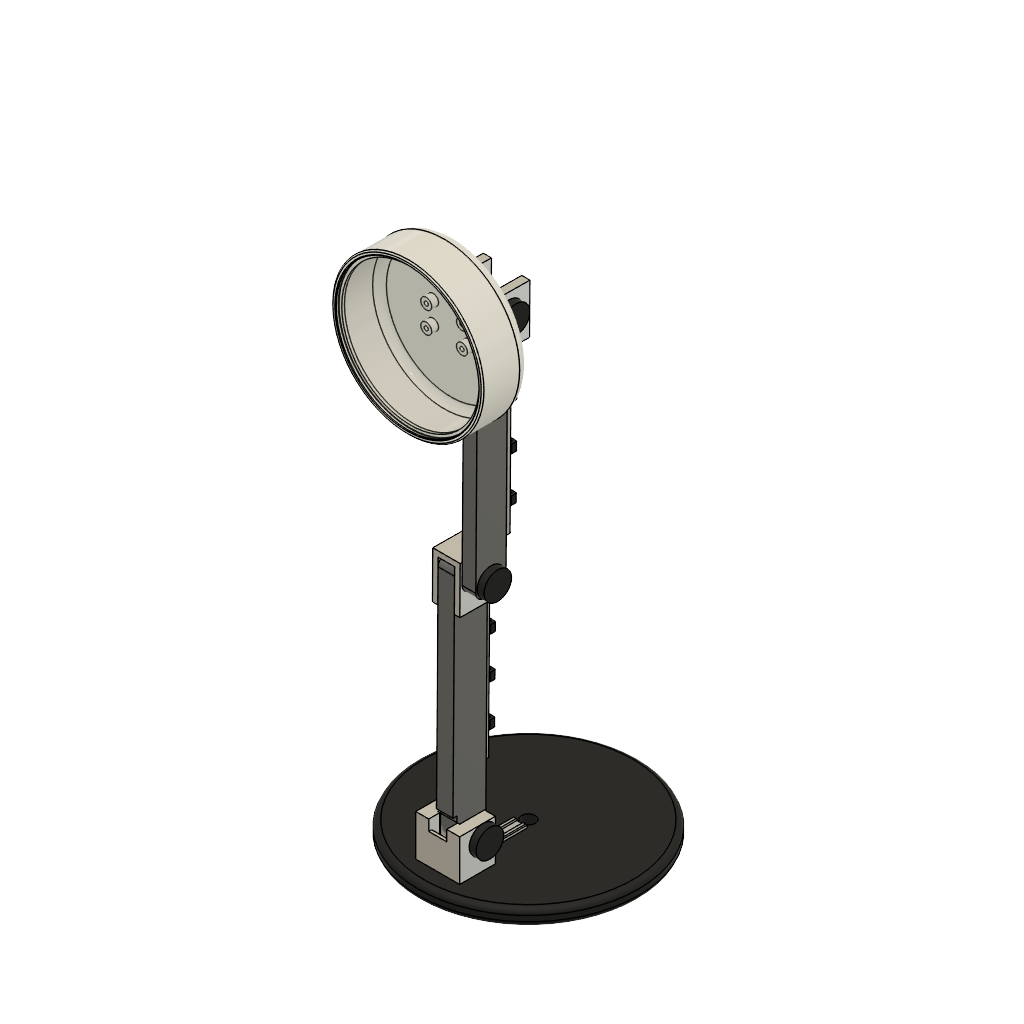
Desk_Lamp (Autodesk Fusion 360 design; units mm, degrees)
part number: 2026-11-22-08-35-22-088
part number: 2026-11-22-08-41-16-784
part number: 2026-11-22-08-41-16-816
part number: 2026-11-22-08-49-23-642
part number: 2026-11-22-08-49-23-668
part number: 2026-11-22-08-49-23-682
part number: 2026-11-22-09-13-58-178
part number: 2026-11-22-09-13-58-192
part number: 2026-11-22-09-13-58-206
part number: 2026-11-22-09-13-58-223
part number: 2026-11-22-09-22-23-851
part number: 2026-11-22-09-22-23-900
part number: 2026-11-22-09-22-23-921
part number: 2026-11-22-10-07-11-432
part number: 2026-11-22-10-07-39-371
part number: 2026-11-22-10-07-39-543
part number: 2026-11-22-10-22-32-254
part number: 2026-11-22-10-22-32-761
part number: 2026-11-22-10-22-33-482
part number: 2026-11-22-10-22-33-910
part number: 2026-11-22-10-22-34-385
part number: 2026-11-22-10-23-03-313
part number: 2026-11-22-10-23-03-986
part number: 2026-11-22-10-23-04-519
part number: 2026-11-22-10-23-04-941
Autodesk Fusion 360 part; units mm, degrees
sketch "Base Profile" plane through (0, 0, 0) normal (0, 0, 1) x (1, 0, 0) in component "Circular Base"
  circle A0 centre (0, 0) radius 80
extrude "Extrude1" add sketch "Base Profile" along normal blind 12 makes body 1 in component "Circular Base"
fillet "Fillet1" radius 4 2 edges at (-74.5862, -28.9292, 12) (-74.5862, -28.9292, 0) on bodies 1 in component "Circular Base"
sketch "Cable Hole" plane through (0, 0, 0) normal (0, 0, 1) x (1, 0, 0) in component "Circular Base"
  circle A0 centre (0, 0) radius 5
extrude "Extrude2" cut sketch "Cable Hole" along normal blind 12 bodies 1 in component "Circular Base"
sketch "Grip Recesses" plane through (0, 0, 0) normal (0, 0, 1) x (1, 0, 0) in component "Circular Base"
  circle A0 centre (42.4264, 42.4264) radius 7
  circle A1 centre (-42.4264, 42.4264) radius 7
  circle A2 centre (-42.4264, -42.4264) radius 7
  circle A3 centre (42.4264, -42.4264) radius 7
extrude "Extrude3" cut sketch "Grip Recesses" along normal blind 1.5 bodies 1 in component "Circular Base"
ref_plane "WorkPlane1" through (0, 0, 12) normal (0, 0, 1) x (1, 0, 0) in component "Base Support Bracket"
sketch "U Bracket Profile" plane through (0, 0, 12) normal (0, 0, 1) x (1, 0, 0) in component "Base Support Bracket"
  line L0 (-16, -66) -> (16, -66)
  line L1 (16, -66) -> (16, -40)
  line L2 (16, -40) -> (8, -40)
  line L3 (8, -40) -> (8, -58)
  line L4 (8, -58) -> (-8, -58)
  line L5 (-8, -58) -> (-8, -40)
  line L6 (-8, -40) -> (-16, -40)
  line L7 (-16, -40) -> (-16, -66)
extrude "Extrude1'" add sketch "U Bracket Profile" along normal blind 30 separate body makes body 2 in component "Base Support Bracket"
sketch "Pivot Holes" plane through (0, 0, 0) normal (1, 0, 0) x (0, 0, -1) in component "Base Support Bracket"
  circle A0 centre (-32, -49) radius 3
extrude "Extrude2'" cut sketch "Pivot Holes" along normal blind 20 and the other way blind 20 bodies 2 in component "Base Support Bracket"
sketch "Arm Profile" plane through (0, 0, 0) normal (1, 0, 0) x (0, 0, -1) in component "Lower Arm"
  line L0 (-30.1557, 18.8328) -> (149.8443, 18.8328)
  line L1 (149.8443, 18.8328) -> (149.8443, 42.8328)
  line L2 (149.8443, 42.8328) -> (-30.1557, 42.8328)
  line L3 (-30.1557, 42.8328) -> (-30.1557, 18.8328)
extrude "Extrude1''" add sketch "Arm Profile" along normal mid plane 12 separate body makes body 3 in component "Lower Arm"
fillet "Fillet1'" radius 6 4 edges at (0, 42.8328, 30.1557) (0, 42.8328, -149.8443) (0, 18.8328, -149.8443) (0, 18.8328, 30.1557) on bodies 3 in component "Lower Arm"
sketch "Arm Pivot Holes" plane through (0, 0, 0) normal (1, 0, 0) x (0, 0, -1) in component "Lower Arm"
  circle A0 centre (-22.1557, 30.8328) radius 3
  circle A1 centre (141.8443, 30.8328) radius 3
extrude "Extrude2''" cut sketch "Arm Pivot Holes" along normal mid plane 12 bodies 3 in component "Lower Arm"
sketch "Pin Profile" plane through (0, 0, 0) normal (1, 0, 0) x (0, 0, -1) in component "Base Pivot Pin"
  circle A0 centre (-22.1557, 30.8328) radius 3
extrude "Extrude1'''" add sketch "Pin Profile" along normal mid plane 32 separate body makes body 4 in component "Base Pivot Pin"
ref_plane "WorkPlane1" through (16, 0, 0) normal (1, 0, 0) x (0, 1, 0) in component "Adjustment Knob"
sketch "Knob Profile" plane through (16, 0, 0) normal (1, 0, 0) x (0, 0, -1) in component "Adjustment Knob"
  circle A0 centre (-22.1557, 30.8328) radius 10
extrude "Extrude1''''" add sketch "Knob Profile" along normal blind 5 separate body makes body 5 in component "Adjustment Knob"
ref_plane "WorkPlane1" through (15.5, 0, 0) normal (1, 0, 0) x (0, 1, 0) in component "Upper Arm"
sketch "Upper Arm Profile" plane through (15.5, 0, 0) normal (1, 0, 0) x (0, 0, -1) in component "Upper Arm"
  line L0 (133.8443, 19.8328) -> (293.8443, 19.8328)
  line L1 (293.8443, 19.8328) -> (293.8443, 41.8328)
  line L2 (293.8443, 41.8328) -> (133.8443, 41.8328)
  line L3 (133.8443, 41.8328) -> (133.8443, 19.8328)
extrude "Extrude1'''''" add sketch "Upper Arm Profile" along normal mid plane 10 separate body makes body 6 in component "Upper Arm"
fillet "Fillet1''" radius 6 4 edges at (15.5, 41.8328, -133.8443) (15.5, 41.8328, -293.8443) (15.5, 19.8328, -293.8443) (15.5, 19.8328, -133.8443) on bodies 6 in component "Upper Arm"
sketch "Upper Arm Pivot Holes" plane through (15.5, 0, 0) normal (1, 0, 0) x (0, 0, -1) in component "Upper Arm"
  circle A0 centre (141.8443, 30.8328) radius 3
  circle A1 centre (285.8443, 30.8328) radius 3
extrude "Extrude2'''" cut sketch "Upper Arm Pivot Holes" along normal mid plane 10 bodies 6 in component "Upper Arm"
ref_plane "WorkPlane1" through (0, 30.8328, 0) normal (0, 1, 0) x (0, 0, 1) in component "Elbow Joint Connector"
sketch "Clevis Profile" plane through (0, 30.8328, 0) normal (0, 1, 0) x (1, 0, 0) in component "Elbow Joint Connector"
  line L0 (-10, 153.8443) -> (10, 153.8443)
  line L1 (10, 153.8443) -> (10, 119.8443)
  line L2 (10, 119.8443) -> (6, 119.8443)
  line L3 (6, 119.8443) -> (6, 149.8443)
  line L4 (6, 149.8443) -> (-6, 149.8443)
  line L5 (-6, 149.8443) -> (-6, 119.8443)
  line L6 (-6, 119.8443) -> (-10, 119.8443)
  line L7 (-10, 119.8443) -> (-10, 153.8443)
extrude "Extrude1''''''" add sketch "Clevis Profile" along normal mid plane 24 separate body makes body 7 in component "Elbow Joint Connector"
sketch "Clevis Pivot Holes" plane through (0, 0, 0) normal (1, 0, 0) x (0, 0, -1) in component "Elbow Joint Connector"
  circle A0 centre (141.8443, 30.8328) radius 3
extrude "Extrude2''''" cut sketch "Clevis Pivot Holes" along normal mid plane 20 bodies 7 in component "Elbow Joint Connector"
ref_plane "WorkPlane1" through (5.25, 0, 0) normal (1, 0, 0) x (0, 1, 0) in component "Elbow Pivot Pin"
sketch "Elbow Pin Profile" plane through (5.25, 0, 0) normal (1, 0, 0) x (0, 0, -1) in component "Elbow Pivot Pin"
  circle A0 centre (141.8443, 30.8328) radius 3
extrude "Extrude1'''''''" add sketch "Elbow Pin Profile" along normal mid plane 30.5 separate body makes body 8 in component "Elbow Pivot Pin"
ref_plane "WorkPlane1" through (23, 0, 0) normal (1, 0, 0) x (0, 1, 0) in component "Elbow Adjustment Knob"
sketch "Elbow Knob Profile" plane through (23, 0, 0) normal (1, 0, 0) x (0, 0, -1) in component "Elbow Adjustment Knob"
  circle A0 centre (141.8443, 30.8328) radius 10
extrude "Extrude1''''''''" add sketch "Elbow Knob Profile" along normal mid plane 5 separate body makes body 9 in component "Elbow Adjustment Knob"
ref_plane "WorkPlane1" through (0, 30.8328, 0) normal (0, 1, 0) x (0, 0, 1) in component "Head Support Bracket"
sketch "Head Bracket Profile" plane through (0, 30.8328, 0) normal (0, 1, 0) x (1, 0, 0) in component "Head Support Bracket"
  line L0 (-1.5, 293.8443) -> (32.5, 293.8443)
  line L1 (32.5, 293.8443) -> (32.5, 329.8443)
  line L2 (32.5, 329.8443) -> (26.5, 329.8443)
  line L3 (26.5, 329.8443) -> (26.5, 299.8443)
  line L4 (26.5, 299.8443) -> (4.5, 299.8443)
  line L5 (4.5, 299.8443) -> (4.5, 329.8443)
  line L6 (4.5, 329.8443) -> (-1.5, 329.8443)
  line L7 (-1.5, 329.8443) -> (-1.5, 293.8443)
extrude "Extrude1'''''''''" add sketch "Head Bracket Profile" along normal mid plane 30 separate body makes body 10 in component "Head Support Bracket"
ref_plane "WorkPlane2" through (15.5, 0, 0) normal (1, 0, 0) x (0, 1, 0) in component "Head Support Bracket"
sketch "Head Pivot Holes" plane through (15.5, 0, 0) normal (1, 0, 0) x (0, 0, -1) in component "Head Support Bracket"
  circle A0 centre (314.8443, 30.8328) radius 3
extrude "Extrude2'''''" cut sketch "Head Pivot Holes" along normal mid plane 40 bodies 10 in component "Head Support Bracket"
ref_plane "WorkPlane1" through (15.5, 0, 0) normal (1, 0, 0) x (0, 1, 0) in component "Head Pivot Pin"
sketch "Head Pin Profile" plane through (15.5, 0, 0) normal (1, 0, 0) x (0, 0, -1) in component "Head Pivot Pin"
  circle A0 centre (314.8443, 30.8328) radius 3
extrude "Extrude1''''''''''" add sketch "Head Pin Profile" along normal mid plane 34 separate body makes body 11 in component "Head Pivot Pin"
ref_plane "WorkPlane1" through (35, 0, 0) normal (1, 0, 0) x (0, 1, 0) in component "Head Adjustment Knob"
sketch "Head Knob Profile" plane through (35, 0, 0) normal (1, 0, 0) x (0, 0, -1) in component "Head Adjustment Knob"
  circle A0 centre (314.8443, 30.8328) radius 10
extrude "Extrude1'''''''''''" add sketch "Head Knob Profile" along normal mid plane 5 separate body makes body 12 in component "Head Adjustment Knob"
ref_plane "WorkPlane1" through (0, 0, 42) normal (0, 0, 1) x (1, 0, 0) in component "Lamp Housing"
sketch "Housing Outer Profile" plane through (0, 0, 42) normal (0, 0, 1) x (1, 0, 0) in component "Lamp Housing"
  circle A0 centre (15.5, 367.82) radius 55
extrude "Extrude1''''''''''''" add sketch "Housing Outer Profile" along normal blind 35 separate body makes body 13 in component "Lamp Housing"
fillet "Fillet1'''" radius 8 1 edges at (-35.778, 347.9312, 42) on bodies 13 in component "Lamp Housing"
shell "Shell1" thickness 3 removed faces 1 at (3.0683, 340.128, 77) on bodies 13 in component "Lamp Housing"
ref_plane "WorkPlane2" through (0, 0, 77) normal (0, 0, 1) x (1, 0, 0) in component "Lamp Housing"
sketch "Cover Recess" plane through (0, 0, 77) normal (0, 0, 1) x (1, 0, 0) in component "Lamp Housing"
  circle A0 centre (15.5, 367.82) radius 52.5
extrude "Extrude2''''''" cut sketch "Cover Recess" against normal blind 2.5 bodies 13 in component "Lamp Housing"
ref_plane "WorkPlane3" through (0, 0, 72.5) normal (0, 0, 1) x (1, 0, 0) in component "Lamp Housing"
sketch "Cover Ledge" plane through (0, 0, 72.5) normal (0, 0, 1) x (1, 0, 0) in component "Lamp Housing"
  circle A0 centre (15.5, 367.82) radius 53
  circle A1 centre (15.5, 367.82) radius 50
extrude "Extrude3'" add sketch "Cover Ledge" along normal blind 2 bodies 13 in component "Lamp Housing"
fillet "Fillet2" radius 1 1 edges at (-35.778, 347.9312, 77) on bodies 13 in component "Lamp Housing"
ref_plane "WorkPlane4" through (0, 0, 45) normal (0, 0, 1) x (1, 0, 0) in component "Lamp Housing"
sketch "Mounting Bosses" plane through (0, 0, 45) normal (0, 0, 1) x (1, 0, 0) in component "Lamp Housing"
  circle A0 centre (2.5, 360.02) radius 4
  circle A1 centre (2.5, 375.62) radius 4
  circle A2 centre (28.5, 360.02) radius 4
  circle A3 centre (28.5, 375.62) radius 4
extrude "Extrude4" add sketch "Mounting Bosses" along normal blind 5 bodies 13 in component "Lamp Housing"
ref_plane "WorkPlane5" through (0, 0, 50) normal (0, 0, 1) x (1, 0, 0) in component "Lamp Housing"
sketch "Mounting Holes" plane through (0, 0, 50) normal (0, 0, 1) x (1, 0, 0) in component "Lamp Housing"
  circle A0 centre (2.5, 360.02) radius 1.5
  circle A1 centre (2.5, 375.62) radius 1.5
  circle A2 centre (28.5, 360.02) radius 1.5
  circle A3 centre (28.5, 375.62) radius 1.5
extrude "Extrude5" cut sketch "Mounting Holes" against normal blind 8 bodies 13 in component "Lamp Housing"
ref_plane "WorkPlane1" through (0, 0, 74.5) normal (0, 0, 1) x (1, 0, 0) in component "Front Cover"
sketch "Cover Profile" plane through (0, 0, 74.5) normal (0, 0, 1) x (1, 0, 0) in component "Front Cover"
  circle A0 centre (15.5, 367.82) radius 52
extrude "Extrude1'''''''''''''" add sketch "Cover Profile" along normal blind 2 separate body makes body 14 in component "Front Cover"
ref_plane "WorkPlane1" through (5.5, 0, 0) normal (1, 0, 0) x (0, 1, 0) in component "Mounting Connector"
sketch "Tilt Lug Neck" plane through (5.5, 0, 0) normal (1, 0, 0) x (0, 0, -1) in component "Mounting Connector"
  line L0 (-19.57, 359.82) -> (-41, 359.82)
  line L1 (-41, 359.82) -> (-41, 375.82)
  line L2 (-41, 375.82) -> (-19.57, 375.82)
  line L3 (-19.57, 375.82) -> (-19.57, 359.82)
extrude "Extrude1''''''''''''''" add sketch "Tilt Lug Neck" along normal blind 20 separate body makes body 15 in component "Mounting Connector"
sketch "Tilt Lug Eye" plane through (5.5, 0, 0) normal (1, 0, 0) x (0, 0, -1) in component "Mounting Connector"
  circle A0 centre (-19.57, 367.82) radius 8
extrude "Extrude2'''''''" add sketch "Tilt Lug Eye" along normal blind 20 bodies 15 in component "Mounting Connector"
sketch "Pivot Hole" plane through (5.5, 0, 0) normal (1, 0, 0) x (0, 0, -1) in component "Mounting Connector"
  circle A0 centre (-19.57, 367.82) radius 3.1
extrude "Extrude2''''''''" cut sketch "Pivot Hole" along normal blind 20 sketch seen with x (1, 0, 0) y (0, 0.00766, -0.999971) z (0, 0.999971, 0.00766) at (0, 8.4415, 52.8179) bodies 11 makes body 16 at (3.1667, 33.5024, -316.2129) in component "Head Pivot Pin"
extrude "Extrude3''" cut sketch "Pivot Hole" along normal blind 20 bodies 15 in component "Mounting Connector"
ref_plane "WorkPlane2" through (0, 0, 40) normal (0, 0, 1) x (1, 0, 0) in component "Mounting Connector"
sketch "Mounting Flange" plane through (0, 0, 40) normal (0, 0, 1) x (1, 0, 0) in component "Mounting Connector"
  line L0 (-1.5, 355.82) -> (32.5, 355.82)
  line L1 (32.5, 355.82) -> (32.5, 379.82)
  line L2 (32.5, 379.82) -> (-1.5, 379.82)
  line L3 (-1.5, 379.82) -> (-1.5, 355.82)
extrude "Extrude4'" add sketch "Mounting Flange" along normal blind 2 bodies 15 in component "Mounting Connector"
ref_plane "WorkPlane3" through (0, 0, 42) normal (0, 0, 1) x (1, 0, 0) in component "Mounting Connector"
sketch "Flange Screw Holes" plane through (0, 0, 42) normal (0, 0, 1) x (1, 0, 0) in component "Mounting Connector"
  circle A0 centre (2.5, 360.02) radius 1.5
  circle A1 centre (2.5, 375.62) radius 1.5
  circle A2 centre (28.5, 360.02) radius 1.5
  circle A3 centre (28.5, 375.62) radius 1.5
extrude "Extrude5'" cut sketch "Flange Screw Holes" against normal blind 2 bodies 15 in component "Mounting Connector"
ref_plane "WorkPlane2" through (0, 0.33, 0) normal (0, 1, 0) x (0, 0, 1) in component "Rubber Grip Pad"
sketch "Pad Profile" plane through (0, 0.33, 0) normal (0, 1, 0) x (1, 0, 0) in component "Rubber Grip Pad"
  circle A0 centre (42.43, -15.58) radius 7
extrude "Extrude1'''''''''''''''" add sketch "Pad Profile" against normal blind 2 separate body makes body 17 in component "Rubber Grip Pad"
fillet "Fillet1''''" radius 0.5 1 edges at (35.9037, -1.67, 13.0487) on bodies 17 in component "Rubber Grip Pad"
ref_plane "WorkPlane2" through (0, 10.83, 0) normal (0, 1, 0) x (0, 0, 1) in component "Base Cable Guide"
sketch "Guide Profile" plane through (0, 10.83, 0) normal (0, 1, 0) x (1, 0, 0) in component "Base Cable Guide"
  line L0 (-5, 21) -> (5, 21)
  line L1 (5, 21) -> (5, -12)
  line L2 (5, -12) -> (-5, -12)
  line L3 (-5, -12) -> (-5, 21)
extrude "Extrude1''''''''''''''''" add sketch "Guide Profile" along normal blind 2.5 separate body makes body 18 in component "Base Cable Guide"
fillet "Fillet1'''''" radius 0.6 4 edges at (0, 13.33, 12) (5, 13.33, -4.5) (0, 13.33, -21) (-5, 13.33, -4.5) on bodies 18 in component "Base Cable Guide"
ref_plane "WorkPlane3" through (0, 13.33, 0) normal (0, 1, 0) x (0, 0, 1) in component "Base Cable Guide"
sketch "Guide Groove" plane through (0, 13.33, 0) normal (0, 1, 0) x (1, 0, 0) in component "Base Cable Guide"
  line L0 (-2.5, 23) -> (2.5, 23)
  line L1 (2.5, 23) -> (2.5, -14)
  line L2 (2.5, -14) -> (-2.5, -14)
  line L3 (-2.5, -14) -> (-2.5, 23)
extrude "Extrude2'''''''''" cut sketch "Guide Groove" against normal blind 1.5 bodies 18 in component "Base Cable Guide"
ref_plane "WorkPlane1" through (0, 0, 42) normal (0, 0, 1) x (1, 0, 0) in component "Housing Rear Cable Anchor"
sketch "Anchor Profile" plane through (0, 0, 42) normal (0, 0, 1) x (1, 0, 0) in component "Housing Rear Cable Anchor"
  circle A0 centre (15.5, 400) radius 6
extrude "Extrude1'''''''''''''''''" add sketch "Anchor Profile" against normal blind 5 separate body makes body 19 in component "Housing Rear Cable Anchor"
fillet "Fillet1''''''" radius 0.8 1 edges at (9.906, 402.1697, 37) on bodies 19 in component "Housing Rear Cable Anchor"
ref_plane "WorkPlane2" through (0, 0, 37) normal (0, 0, 1) x (1, 0, 0) in component "Housing Rear Cable Anchor"
sketch "Anchor Bore" plane through (0, 0, 37) normal (0, 0, 1) x (1, 0, 0) in component "Housing Rear Cable Anchor"
  circle A0 centre (15.5, 400) radius 3
extrude "Extrude2''''''''''" cut sketch "Anchor Bore" along normal blind 4 bodies 19 in component "Housing Rear Cable Anchor"
ref_plane "WorkPlane2" through (-16, 0, 0) normal (1, 0, 0) x (0, 1, 0) in component "Base Pivot Cover"
sketch "Cap Profile" plane through (-16, 0, 0) normal (1, 0, 0) x (0, 0, -1) in component "Base Pivot Cover"
  circle A0 centre (-22.16, 30.83) radius 5.5
extrude "Extrude1''''''''''''''''''" add sketch "Cap Profile" against normal blind 2 separate body makes body 20 in component "Base Pivot Cover"
fillet "Fillet1'''''''" radius 0.8 1 edges at (-18, 32.8189, 27.2878) on bodies 20 in component "Base Pivot Cover"
ref_plane "WorkPlane2" through (-1.5, 0, 0) normal (1, 0, 0) x (0, 1, 0) in component "Head Pivot Cover"
sketch "Cap Profile (2)" plane through (-1.5, 0, 0) normal (1, 0, 0) x (0, 0, -1) in component "Head Pivot Cover"
  circle A0 centre (-19.57, 367.82) radius 5.5
extrude "Extrude1'''''''''''''''''''" add sketch "Cap Profile (2)" against normal blind 2 separate body makes body 21 in component "Head Pivot Cover"
fillet "Fillet1''''''''" radius 0.8 1 edges at (-3.5, 369.8089, 24.6978) on bodies 21 in component "Head Pivot Cover"
ref_plane "WorkPlane1" through (0, 0, -116) normal (0, 0, 1) x (1, 0, 0) in component "Lower Arm Cable Channel"
sketch "Channel Profile" plane through (0, 0, -116) normal (0, 0, 1) x (1, 0, 0) in component "Lower Arm Cable Channel"
  line L0 (-4.5, 14.8) -> (4.5, 14.8)
  line L1 (4.5, 14.8) -> (4.5, 18.8)
  line L2 (4.5, 18.8) -> (-4.5, 18.8)
  line L3 (-4.5, 18.8) -> (-4.5, 14.8)
extrude "Extrude1''''''''''''''''''''" add sketch "Channel Profile" along normal blind 100 separate body makes body 22 in component "Lower Arm Cable Channel"
fillet "Fillet1'''''''''" radius 0.8 4 edges at (0, 14.8, -116) (4.5, 14.8, -66) (0, 14.8, -16) (-4.5, 14.8, -66) on bodies 22 in component "Lower Arm Cable Channel"
ref_plane "WorkPlane2" through (0, 0, -117) normal (0, 0, 1) x (1, 0, 0) in component "Lower Arm Cable Channel"
sketch "Cable Groove" plane through (0, 0, -117) normal (0, 0, 1) x (1, 0, 0) in component "Lower Arm Cable Channel"
  line L0 (-2.5, 14.3) -> (2.5, 14.3)
  line L1 (2.5, 14.3) -> (2.5, 17.3)
  line L2 (2.5, 17.3) -> (-2.5, 17.3)
  line L3 (-2.5, 17.3) -> (-2.5, 14.3)
extrude "Extrude2'''''''''''" cut sketch "Cable Groove" along normal blind 102 bodies 22 in component "Lower Arm Cable Channel"
ref_plane "WorkPlane1" through (0, 0, -270) normal (0, 0, 1) x (1, 0, 0) in component "Upper Arm Cable Channel"
sketch "Channel Profile (2)" plane through (0, 0, -270) normal (0, 0, 1) x (1, 0, 0) in component "Upper Arm Cable Channel"
  line L0 (11, 15.8) -> (20, 15.8)
  line L1 (20, 15.8) -> (20, 19.8)
  line L2 (20, 19.8) -> (11, 19.8)
  line L3 (11, 19.8) -> (11, 15.8)
extrude "Extrude1'''''''''''''''''''''" add sketch "Channel Profile (2)" along normal blind 105 separate body makes body 23 in component "Upper Arm Cable Channel"
fillet "Fillet1''''''''''" radius 0.8 4 edges at (15.5, 15.8, -270) (20, 15.8, -217.5) (15.5, 15.8, -165) (11, 15.8, -217.5) on bodies 23 in component "Upper Arm Cable Channel"
ref_plane "WorkPlane2" through (0, 0, -271) normal (0, 0, 1) x (1, 0, 0) in component "Upper Arm Cable Channel"
sketch "Cable Groove (2)" plane through (0, 0, -271) normal (0, 0, 1) x (1, 0, 0) in component "Upper Arm Cable Channel"
  line L0 (13, 15.3) -> (18, 15.3)
  line L1 (18, 15.3) -> (18, 18.3)
  line L2 (18, 18.3) -> (13, 18.3)
  line L3 (13, 18.3) -> (13, 15.3)
extrude "Extrude2''''''''''''" cut sketch "Cable Groove (2)" along normal blind 107 bodies 23 in component "Upper Arm Cable Channel"
ref_plane "WorkPlane1" through (0, 0, -3) normal (0, 0, 1) x (1, 0, 0) in component "Cable Clip"
sketch "Clip Profile" plane through (0, 0, -3) normal (0, 0, 1) x (1, 0, 0) in component "Cable Clip"
  line L0 (-4.5, 14.8) -> (-4.5, 10.8)
  line L1 (-4.5, 10.8) -> (4.5, 10.8)
  line L2 (4.5, 10.8) -> (4.5, 14.8)
  line L3 (4.5, 14.8) -> (2.5, 14.8)
  line L4 (2.5, 14.8) -> (2.5, 12.3)
  line L5 (2.5, 12.3) -> (-2.5, 12.3)
  line L6 (-2.5, 12.3) -> (-2.5, 14.8)
  line L7 (-2.5, 14.8) -> (-4.5, 14.8)
extrude "Extrude1''''''''''''''''''''''" add sketch "Clip Profile" along normal blind 6 separate body makes body 24 in component "Cable Clip"
fillet "Fillet1'''''''''''" radius 0.5 2 edges at (4.5, 10.8, 0) (-4.5, 10.8, 0) on bodies 24 in component "Cable Clip"
ref_plane "WorkPlane1" through (-10, 0, 0) normal (1, 0, 0) x (0, 1, 0) in component "Elbow Pivot Cover"
sketch "Cap Profile (3)" plane through (-10, 0, 0) normal (1, 0, 0) x (0, 0, -1) in component "Elbow Pivot Cover"
  circle A0 centre (141.8, 30.8) radius 5.5
extrude "Extrude1'''''''''''''''''''''''" add sketch "Cap Profile (3)" against normal blind 2 separate body makes body 25 in component "Elbow Pivot Cover"
fillet "Fillet1''''''''''''" radius 0.8 1 edges at (-12, 32.7889, -136.6722) on bodies 25 in component "Elbow Pivot Cover"
ref_plane "WorkPlane3" through (0, -58.0033, 0) normal (0, 1, 0) x (0, 0, 1) in component "Base Support Bracket"
sketch "Arm Clearance Pocket" plane through (0, -58.0033, 0) normal (0, 1, 0) x (1, 0, 0) in component "Base Support Bracket"
  line L0 (-6.5, -21.1667) -> (6.5, -21.1667)
  line L1 (6.5, -21.1667) -> (6.5, -45.1667)
  line L2 (6.5, -45.1667) -> (-6.5, -45.1667)
  line L3 (-6.5, -45.1667) -> (-6.5, -21.1667)
extrude "Extrude3'''" cut sketch "Arm Clearance Pocket" against normal blind 5.84 bodies 2 in component "Base Support Bracket"
extrude "Extrude3''''" cut sketch "Arm Clearance Pocket" against normal blind 5.84 sketch seen with x (1, 0, 0) y (0, -0.999971, -0.00766) z (0, 0.00766, -0.999971) at (0, -18.41, 53.7789) bodies 3 in component "Lower Arm"
ref_plane "WorkPlane5" through (0, -58.0033, 0) normal (0, 1, 0) x (0, 0, 1) in component "Base Support Bracket"
sketch "Arm Clearance Notch" plane through (0, -58.0033, 0) normal (0, 1, 0) x (1, 0, 0) in component "Base Support Bracket"
  line L0 (-6.5, -34.1667) -> (6.5, -34.1667)
  line L1 (6.5, -34.1667) -> (6.5, -46.1667)
  line L2 (6.5, -46.1667) -> (-6.5, -46.1667)
  line L3 (-6.5, -46.1667) -> (-6.5, -34.1667)
extrude "Extrude4''" cut sketch "Arm Clearance Notch" against normal blind 8.34 bodies 2 in component "Base Support Bracket"
extrude "Extrude4'''" cut sketch "Arm Clearance Notch" against normal blind 8.34 sketch seen with x (1, 0, 0) y (0, -0.999971, -0.00766) z (0, 0.00766, -0.999971) at (0, -18.41, 53.7789) bodies 3 in component "Lower Arm"
component "Base Support Bracket" placed x (1, 0, 0) y (0, 0, -1) z (0, 1, 0) at (0, -1.1667, -26.8433)
component "Circular Base" placed x (1, 0, 0) y (0, 0, -1) z (0, 1, 0) at (0, -1.1667, -26.8433)
component "Lower Arm" placed x (1, 0, 0) y (0, 0.00766, 0.999971) z (0, -0.999971, 0.00766) at (0, 52.7517, -8.8459)
component "Base Pivot Pin" placed x (1, 0, 0) y (0, 1, 0) z (0, 0, 1) at (0, 0, 0)
component "Adjustment Knob" placed x (1, 0, 0) y (0, 1, 0) z (0, 0, 1) at (0, 0, 0)
component "Upper Arm" placed x (1, 0, 0) y (0, 0.00766, 0.999971) z (0, -0.999971, 0.00766) at (0, 52.7517, -8.8459)
component "Elbow Joint Connector" placed x (1, 0, 0) y (0, 0.00766, 0.999971) z (0, -0.999971, 0.00766) at (0, 52.7517, -8.8459)
component "Elbow Pivot Pin" placed x (1, 0, 0) y (0, 0.00766, 0.999971) z (0, -0.999971, 0.00766) at (0, 52.7517, -8.8459)
component "Elbow Adjustment Knob" placed x (1, 0, 0) y (0, 0.00766, 0.999971) z (0, -0.999971, 0.00766) at (0, 52.7517, -8.8459)
component "Head Support Bracket" placed x (1, 0, 0) y (0, 0.00766, 0.999971) z (0, -0.999971, 0.00766) at (0, 52.7517, -8.8459)
component "Head Pivot Pin" placed x (1, 0, 0) y (0, 0.00766, 0.999971) z (0, -0.999971, 0.00766) at (0, 52.7517, -8.8459)
component "Head Adjustment Knob" placed x (1, 0, 0) y (0, 0.00766, 0.999971) z (0, -0.999971, 0.00766) at (0, 52.7517, -8.8459)
component "Lamp Housing" placed x (1, 0, 0) y (0, 1, 0) z (0, 0, 1) at (0, 0, 0)
component "Front Cover" placed x (1, 0, 0) y (0, 1, 0) z (0, 0, 1) at (0, 0, 0)
component "Mounting Connector" placed x (1, 0, 0) y (0, 1, 0) z (0, 0, 1) at (0, 0, 0)
component "Rubber Grip Pad" placed x (1, 0, 0) y (0, 1, 0) z (0, 0, 1) at (0, 0, 0)
component "Base Cable Guide" placed x (1, 0, 0) y (0, 1, 0) z (0, 0, 1) at (0, 0, 0)
component "Housing Rear Cable Anchor" placed x (1, 0, 0) y (0, 1, 0) z (0, 0, 1) at (0, 0, 0)
component "Base Pivot Cover" placed x (1, 0, 0) y (0, 1, 0) z (0, 0, 1) at (0, 0, 0)
component "Head Pivot Cover" placed x (1, 0, 0) y (0, 1, 0) z (0, 0, 1) at (0, 0, 0)
component "Lower Arm Cable Channel" placed x (1, 0, 0) y (0, 0.00766, 0.999971) z (0, -0.999971, 0.00766) at (0, 52.7517, -8.8459)
component "Upper Arm Cable Channel" placed x (1, 0, 0) y (0, 0.00766, 0.999971) z (0, -0.999971, 0.00766) at (0, 52.7517, -8.8459)
component "Cable Clip" placed x (1, 0, 0) y (0, 0.00766, 0.999971) z (0, -0.999971, 0.00766) at (0, 88.7506, -9.1216)
component "Elbow Pivot Cover" placed x (1, 0, 0) y (0, 0.00766, 0.999971) z (0, -0.999971, 0.00766) at (0, 52.7517, -8.8459)
component "Rubber Grip Pad" placed x (1, 0, 0) y (0, 1, 0) z (0, 0, 1) at (-84.86, 0, 0)
component "Rubber Grip Pad" placed x (1, 0, 0) y (0, 1, 0) z (0, 0, 1) at (-84.86, 0, -84.85)
component "Rubber Grip Pad" placed x (1, 0, 0) y (0, 1, 0) z (0, 0, 1) at (0, 0, -84.85)
component "Cable Clip" placed x (1, 0, 0) y (0, 0.00766, 0.999971) z (0, -0.999971, 0.00766) at (0, 118.7497, -9.3514)
component "Cable Clip" placed x (1, 0, 0) y (0, 0.00766, 0.999971) z (0, -0.999971, 0.00766) at (0, 148.7489, -9.5813)
component "Cable Clip" placed x (1, 0, 0) y (0, 0.00766, 0.999971) z (0, -0.999971, 0.00766) at (15.5, 237.7539, -9.2631)
component "Cable Clip" placed x (1, 0, 0) y (0, 0.00766, 0.999971) z (0, -0.999971, 0.00766) at (15.5, 270.2529, -9.512)
component "Cable Clip" placed x (1, 0, 0) y (0, 0.00766, 0.999971) z (0, -0.999971, 0.00766) at (15.5, 302.752, -9.761)
equation "d76 = -( 2.50 mm )"
equation "d90 = -( 8.00 mm )"
equation "d112 = -( 2.00 mm )"
equation "d120 = -( 2.00 mm )"
equation "d134 = -( 1.50 mm )"
equation "d138 = -( 5.00 mm )"
equation "d150 = -( 2.00 mm )"
equation "d158 = -( 2.00 mm )"
equation "d190 = -( 2.00 mm )"
equation "d202 = -( 5.84 mm )"
equation "d204 = -( 5.84 mm )"
equation "d210 = -( 8.34 mm )"
equation "d212 = -( 8.34 mm )"
named bodies: "Circular Base", "Base Support Bracket", "Lower Arm", "Base Pivot Pin", "Adjustment Knob", "Upper Arm", "Elbow Joint Connector", "Elbow Pivot Pin", "Elbow Adjustment Knob", "Head Support Bracket", "Head Pivot Pin", "Head Adjustment Knob", "Lamp Housing Body", "Front Cover Body", "Mounting Connector Body", "Head Pivot Pin (1)", "Rubber Grip Pad Body", "Base Cable Guide Body", "Housing Rear Cable Anchor Body", "Base Pivot Cover Body", "Head Pivot Cover Body", "Lower Arm Cable Channel Body", "Upper Arm Cable Channel Body", "Cable Clip Body", "Elbow Pivot Cover Body"
